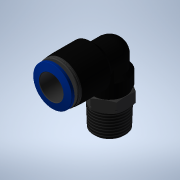
# Autodesk Inventor part: 153053 QSL-3/8-12
Saved by Autodesk Inventor 2021 (Build 250183000, 183)
## iProperties
Created: 2025-06-04
Part Number: 153053 QSL-3/8-12
Material: Generic
Catalog Web Link: www.cadenas.de
Description: QSL-R-push-in L-fitting
Vendor: FESTO
Document SubType Name: Modeling
Designer: psAdmin
Manufacturer: FESTO
Mass: 38 g
Surface Area: 62.8187 cm^2
Volume: 9.6284 cm^3
Density: 1 g/cm^3
Appearance: PSOLRGB-175-175-175
Category: PARTsolutions
Company: FESTO
Title: 153053 QSL-3/8-12
Author: Cadenas PARTsolutions
Comments: push-in L-fitting
PSOL_IDENT_0: {$CADENAS_DATA/23d-libs/festo/parts/q/qsl/qsl.prj},174 {VTYP=3D},{NB=153053 QSL-3/8-12},{LINA=153053
PSOL_IDENT_1: QSL-3/8-12},{NN=QSL-R},{DATE=02.05.2025 12:38:07},{GEOMDATE=01.04.2025 10:00:39},{VERSION=},{LINEID=
PSOL_IDENT_2: 440},{WBVAR=},{WBNUMERIC=}  {NB=153053 QSL-3/8-12},{LINA=153053 QSL-3/8-12},{KT=DUMMY},{TNR=153053},
PSOL_IDENT_3: {TYP=QSL-3/8-12},{D1=R 3/8},{NENN=10.000},{D2=12},{D5=21.000},{H1=32.500},{H2=12.000},{H3=36.700},{L
PSOL_IDENT_4: 1=29.700},{SW=17.000},{T=23.400},{CNSMASSEXACT=0.0380},{DNC=0},{D11=18.000},{H12=6.000},{D1N=16.662}
PSOL_IDENT_5: ,{ZOLL=3/8},{Z=19.800},{VERS=1},{GTIN=4052568031497},{REACH=Ja},{REACHSVHC=Ja},{REACHHAZSUBS=7439-92
PSOL_IDENT_6: -1},{REACHSCIP=4683995a-6d2d-4183-809b-b444404038eb},{REACHVALDATE=05.03.2025}
NB: 153053 QSL-3/8-12
NN: QSL-R
NT: push-in L-fitting
NBSYN: $TNR. $TYP.
LINA: 153053 QSL-3/8-12
CATALOG: Festo
TNR: 153053
TYP: QSL-3/8-12
D1: R 3/8
D2: 12
D5: 21
H1: 32.5
H2: 12
H3: 36.7
L1: 29.7
SW: 17
T: 23.4
CNSMASSEXACT: 0.038
GTIN: 4052568031497
REACH: Yes
REACHSVHC: Yes
REACHHAZSUBS: 7439-92-1
REACHVALDATE: 05.03.2025
SUPPLIER: FESTO
ARTICLENO: 153053 QSL-3/8-12
BOMINFO: 153053 QSL-3/8-12
CREATOR: CADENAS GmbH
Autodesk Inventor part; units mm, degrees
sketch "Sketch_3" plane through (0, 0, 0) normal (0, 0, 1) x (1, 0, 0)
  line L0 (0, 0) -> (0, 27.85)
  arc A0 (7.35, 20.5) -> (0, 27.85) centre (0, 20.5) ccw
  line L1 (7.35, 20.5) -> (7.35, 15.15)
  line L2 (7.35, 15.15) -> (9, 13.5)
  line L3 (9, 13.5) -> (9, 7.8)
  line L4 (9, 7.8) -> (8.25, 7.5)
  line L5 (8.25, 7.5) -> (8.25, 6)
  line L6 (8.25, 6) -> (8.5, 6)
  line L7 (8.5, 6) -> (10.2, 5.5445)
  line L8 (10.2, 5.5445) -> (10.2, 0.9815)
  line L9 (10.2, 0.9815) -> (8.5, 0)
  line L10 (8.5, 0) -> (0, 0)
  line L11 (0, 0) -> (0, 27.85)
  constraints: 24 end point, 2 point on circle, 1 centre point
revolve "Revolution1" add sketch "Sketch_3" angle 360 about axis through (0, 0, 0) along (0, -1, 0)
sketch "Sketch_19" plane through (0, 0, 0) normal (1, 0, 0) x (0, 1, 0)
  line L0 (20.5, 0) -> (20.5, 29.7)
  line L1 (20.5, 29.7) -> (26.8, 29.7)
  line L2 (26.8, 29.7) -> (30.2347, 29.0944)
  arc A0 (30.4, 28.8974) -> (30.2347, 29.0944) centre (30.2, 28.8974) ccw
  line L3 (30.4, 28.8974) -> (30.4, 27.7)
  line L4 (30.4, 27.7) -> (27.55, 27.7)
  arc A1 (27.55, 27.7) -> (27.25, 27.4) centre (27.55, 27.4) ccw
  line L5 (27.25, 27.4) -> (27.25, 26.2)
  line L6 (27.25, 26.2) -> (30.4, 26.2)
  line L7 (30.4, 26.2) -> (30.7, 25.9)
  line L8 (30.7, 25.9) -> (30.7, 25.2)
  line L9 (30.7, 25.2) -> (30.6, 25.1)
  line L10 (30.6, 25.1) -> (30.7, 25)
  line L11 (30.7, 25) -> (30.7, 24.3)
  line L12 (30.7, 24.3) -> (30.6, 24.2)
  line L13 (30.6, 24.2) -> (30.869, 24.2)
  line L14 (30.869, 24.2) -> (31, 21.7)
  line L15 (31, 21.7) -> (31, 9.8)
  line L16 (31, 9.8) -> (27.85, 6.65)
  line L17 (27.85, 6.65) -> (27.85, 0)
  line L18 (27.85, 0) -> (20.5, 0)
  line L19 (20.5, 0) -> (20.5, 29.7)
  constraints: 40 end point, 4 point on circle, 2 centre point
revolve "Revolution2" add sketch "Sketch_19" angle 360 about axis through (0, 20.5, 0) along (0, 0, -1)
sketch "Sketch_6" plane through (0, 20.5, 0) normal (0, 1, 0) x (1, 0, 0)
  arc A0 (-7.35, -5.194) -> (7.35, -5.194) centre (0, 0) ccw
  line L0 (7.35, -5.194) -> (7.35, 0)
  line L1 (7.35, 0) -> (-7.35, 0)
  line L2 (-7.35, 0) -> (-7.35, -5.194)
  constraints: 6 end point, 2 point on circle, 1 centre point
extrude "Extrusion1" add sketch "Sketch_6" against normal blind 7
sketch "Sketch_12" plane through (0, 0, 0) normal (1, 0, 0) x (0, 1, 0)
  line L0 (15.25, 16.35) -> (3.4, 4.5)
  line L1 (3.4, 4.5) -> (15.25, 4.5)
  line L2 (15.25, 4.5) -> (15.25, 16.35)
  constraints: 6 end point
extrude "Extrusion2" add sketch "Sketch_12" along normal mid plane 3
sketch "Sketch_8" plane through (0, 0, 0) normal (1, 0, 0) x (0, 1, 0)
  line L0 (20.5, 0) -> (20.5, 29.7)
  line L1 (20.5, 29.7) -> (26.8, 29.7)
  arc A0 (26.8, 29.7) -> (26.5, 29.4) centre (26.8, 29.4) ccw
  line L2 (26.5, 29.4) -> (26.5, 6.3)
  line L3 (26.5, 6.3) -> (25.5, 6.3)
  line L4 (25.5, 6.3) -> (25.5, 0)
  arc A1 (20.5, -5) -> (25.5, 0) centre (20.5, 0) ccw
  line L5 (20.5, -5) -> (20.5, 29.7)
  constraints: 12 end point, 4 point on circle, 2 centre point
revolve "Revolution3" cut sketch "Sketch_8" angle 360 about axis through (0, 20.5, 0) along (0, 0, -1)
sketch "Sketch_22" plane through (0, 0, 0) normal (0, 1, 0) x (1, 0, 0)
  line L0 (-17, -17) -> (17, -17)
  line L1 (17, -17) -> (17, 17)
  line L2 (17, 17) -> (-17, 17)
  line L3 (-17, 17) -> (-17, -17)
  line L4 (-8.5, -4.9075) -> (0, -9.815)
  line L5 (0, -9.815) -> (8.5, -4.9075)
  line L6 (8.5, -4.9075) -> (8.5, 4.9075)
  line L7 (8.5, 4.9075) -> (0, 9.815)
  line L8 (0, 9.815) -> (-8.5, 4.9075)
  line L9 (-8.5, 4.9075) -> (-8.5, -4.9075)
  constraints: 20 end point
extrude "Extrusion3" cut sketch "Sketch_22" along normal blind 6
sketch "Sketch_2" plane through (0, 0, 0) normal (0, 0, 1) x (1, 0, 0)
  line L0 (0, 2) -> (0, -2)
  line L1 (-11.615, -0.05) -> (-9.615, 1.95)
  line L2 (-9.615, 1.95) -> (-9.615, 2.25)
  line L3 (-9.615, 2.25) -> (-11.615, 4.25)
  line L4 (-11.615, 4.25) -> (-11.615, -0.05)
  constraints: 10 end point
revolve "Revolution4" cut sketch "Sketch_2" angle 360 about axis through (0, 2, 0) along (0, 1, 0)
sketch "Sketch_23" plane through (0, 0, 0) normal (0, 0, 1) x (1, 0, 0)
  line L0 (0, -12) -> (0, 0)
  line L1 (0, 0) -> (8.5058, 0)
  line L2 (8.5058, 0) -> (8.1588, -11.1164)
  line L3 (8.1588, -11.1164) -> (7.2752, -12)
  line L4 (7.2752, -12) -> (0, -12)
  line L5 (0, -12) -> (0, 0)
  constraints: 12 end point
sketch "Sketch_24" plane through (0, 0, 0) normal (0, 0, 1) x (1, 0, 0)
  line L0 (0, -12) -> (0, 20.5)
  line L1 (0, 20.5) -> (5, 20.5)
  line L2 (5, 20.5) -> (5, -6)
  line L3 (5, -6) -> (5.554, -6)
  line L4 (5.554, -6) -> (5.554, -11.5)
  line L5 (5.554, -11.5) -> (6.054, -12)
  line L6 (6.054, -12) -> (0, -12)
  line L7 (0, -12) -> (0, 20.5)
  constraints: 16 end point
revolve "Revolution5" add sketch "Sketch_23" angle 360 about axis through (0, -12, 0) along (0, -1, 0)
thread "Thread1" size "R 3/8" standard "ISO Taper" full length
revolve "Revolution6" cut sketch "Sketch_24" angle 360 about axis through (0, -12, 0) along (0, -1, 0)
ref_plane "ANBAU_FDT3D_XY" through (0, -5.7, 0) normal (0, -1, 0) x (0, 0, 1)
ref_plane "ANBAU_FDT3D_YZ" through (0, -5.7, 0) normal (0, 0, 1) x (-1, 0, 0)
ref_plane "ANBAU_FDT3D_ZX" through (0, -5.7, 0) normal (-1, 0, 0) x (0, -1, 0)
ref_plane "ANBAU_STD_XY" through (0, -5.7, 0) normal (0, 1, 0) x (0, 0, 1)
ref_plane "ANBAU_STD_YZ" through (0, -5.7, 0) normal (0, 0, 1) x (1, 0, 0)
ref_plane "ANBAU_STD_ZX" through (0, -5.7, 0) normal (1, 0, 0) x (0, 1, 0)
ref_plane "DNC_XY" through (0, 0, 0) normal (0, -1, 0) x (0, 0, 1)
ref_plane "DNC_YZ" through (0, 0, 0) normal (0, 0, 1) x (-1, 0, 0)
ref_plane "DNC_ZX" through (0, 0, 0) normal (-1, 0, 0) x (0, -1, 0)
ref_plane "FDT_SCHLAUCH_XY" through (0, 20.5, 6.3) normal (0, 0, 1) x (1, 0, 0)
ref_plane "FDT_SCHLAUCH_YZ" through (0, 20.5, 6.3) normal (1, 0, 0) x (0, 1, 0)
ref_plane "FDT_SCHLAUCH_ZX" through (0, 20.5, 6.3) normal (0, 1, 0) x (0, 0, 1)
ref_plane "Verschraubung_XY" through (0, -12, 0) normal (0, -1, 0) x (0, 0, 1)
ref_plane "Verschraubung_YZ" through (0, -12, 0) normal (0, 0, 1) x (-1, 0, 0)
ref_plane "Verschraubung_ZX" through (0, -12, 0) normal (-1, 0, 0) x (0, -1, 0)
body "Solid1"
